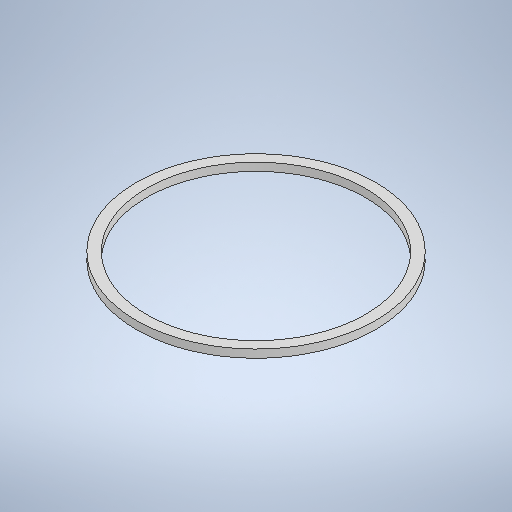
# Autodesk Inventor part: Adapter_LoweredRing
Saved by Autodesk Inventor 2025 (Build 290162000, 162)
## iProperties
Created: 2026-10-28
Part Number: Adapter_LoweredRing
Material: Generic
Document SubType Name: Modeling
Designer: madhami
Density: 1 g/cm^3
Appearance: Default
Author: madhami
Autodesk Inventor part; units mm, degrees
ref_plane "YZ Plane" through (0, 0, 0) normal (1, 0, 0) x (0, 1, 0)
ref_plane "XZ Plane" through (0, 0, 0) normal (0, 1, 0) x (-1, 0, 0)
ref_plane "XY Plane" through (0, 0, 0) normal (0, 0, 1) x (1, 0, 0)
sketch "Sketch1" plane through (0, 0, 0) normal (1, 0, 0) x (0, 1, 0)
  line L0 (0, 0) -> (43.3972, 0)
  line L1 (8, 120.35) -> (0, 120.35)
  line L2 (0, 120.35) -> (0, 117)
  line L3 (0, 117) -> (2, 117)
  line L4 (2, 117) -> (2, 114)
  line L5 (2, 114) -> (0, 114)
  line L6 (0, 114) -> (0, 110)
  line L7 (0, 110) -> (8, 110)
  line L8 (8, 110) -> (8, 120.35)
  dimension "d0" = 3
  dimension "d1" = 240.7
  dimension "d2" = 220
  dimension "d3" = 228
  dimension "d4" = 2
  dimension "d5" = 8
  constraints: 18 end point, 6 perpendicular, 2 horizontal, 2 point on line
  measures "d0" distance of L3.end L4.end
  measures "d1" diameter of L1 L0
  measures "d2" diameter of L7 L0
  measures "d3" diameter of L5 L0
  measures "d4" distance between parallel lines of L6 L4
  measures "d5" distance between parallel lines of L2 L8
revolve "Revolution1" add sketch "Sketch1" angle 360 about axis through (0, 0, 0) along (0, 1, 0)
body "Solid1"
